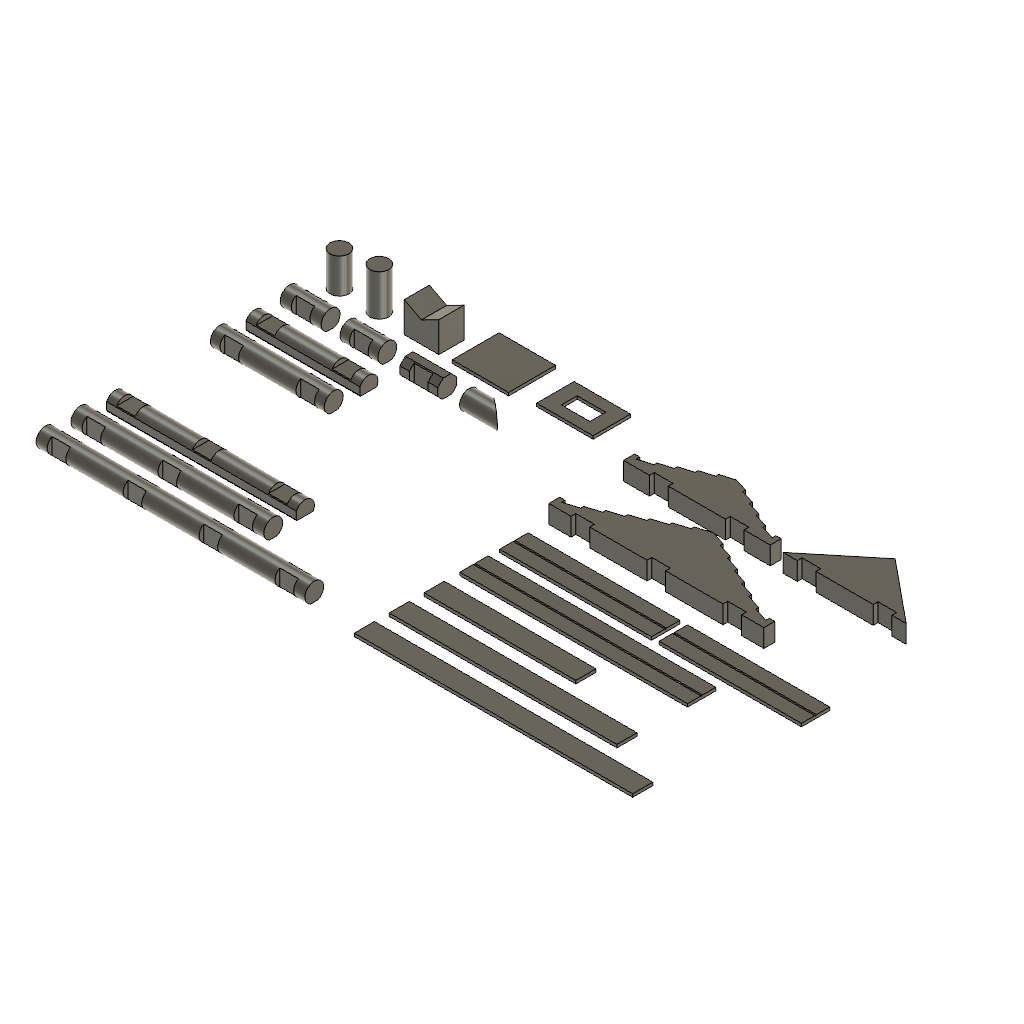
DeadPresidentTreeSections (Autodesk Fusion 360 design; units mm, degrees)
part number: 2026-11-11-17-31-42-128
part number: 2026-11-11-17-31-43-518
part number: 2026-11-11-17-31-43-754
part number: 2026-11-11-17-31-43-862
part number: 2026-11-11-17-31-44-050
part number: 2026-11-11-17-31-44-207
part number: 2026-11-11-17-31-44-370
part number: 2026-11-11-17-31-44-535
part number: 2026-11-11-17-31-44-714
part number: 2026-11-11-17-31-44-916
part number: 2026-11-11-17-31-45-037
part number: 2026-11-11-17-31-45-072
part number: 2026-11-11-17-31-45-145
part number: 2026-11-11-17-31-45-541
part number: 2026-11-11-17-31-45-973
part number: 2026-11-11-17-31-46-214
part number: 2026-11-11-17-31-46-323
part number: 2026-11-11-17-31-46-435
part number: 2026-11-11-17-31-46-554
part number: 2026-11-11-17-31-46-788
part number: 2026-11-11-17-31-47-025
part number: 2026-11-11-17-31-47-289
part number: 2026-11-11-17-31-47-724
part number: 2026-11-11-17-31-47-905
Autodesk Fusion 360 part; units mm, degrees
(part 1 of 2)
sketch "Section" plane through (0, 0, 0) normal (1, 0, 0) x (0, 0, -1) in component "log_1insert_1-5_8"
  circle A0 centre (-8.725, 0) radius 9.525
  line L0 (0, -3.821) -> (0, 3.821)
  dimension "d21" = 8.725
  dimension "d22" = 19.05
  constraint horizontal origin A0.centre
  constraint coincident A0 L0.start
  constraint coincident A0 L0.end
  constraint coincident origin L0
  constraint vertical L0
  measures "d21" horizontal distance of origin A0.centre
  measures "d22" diameter of A0
extrude "Log" add sketch "Section" along normal blind 41.275 contours A0 L0 picked at (-13.8021, 0.6968) makes body 1 in component "log_1insert_1-5_8"
sketch "Notch" plane through (0, 0, 0) normal (0, 0, 1) x (1, 0, 0) in component "log_1insert_1-5_8"
  line L0 (11.3125, 4.7625) -> (29.9625, 4.7625)
  line L1 (29.9625, 4.7625) -> (29.9625, 10.525)
  line L2 (29.9625, 10.525) -> (11.3125, 10.525)
  line L3 (11.3125, 10.525) -> (11.3125, 4.7625)
  line L4 (11.3125, -4.7625) -> (29.9625, -4.7625)
  line L5 (29.9625, -4.7625) -> (29.9625, -10.525)
  line L6 (29.9625, -10.525) -> (11.3125, -10.525)
  line L7 (11.3125, -10.525) -> (11.3125, -4.7625)
  dimension "d25" = 11.3125
  dimension "d26" = 4.7625
  dimension "d27" = 29.9625
  dimension "d28" = 10.525
  dimension "d29" = 11.3125
  dimension "d30" = 4.7625
  dimension "d31" = 29.9625
  dimension "d32" = 10.525
  constraint horizontal L0
  constraint vertical L1
  constraint horizontal L2
  constraint vertical L3
  constraint horizontal L4
  constraint vertical L5
  constraint horizontal L6
  constraint vertical L7
  measures "d25" horizontal distance of origin L0.start
  measures "d26" vertical distance of origin L0.start
  measures "d27" horizontal distance of origin L1.end
  measures "d28" vertical distance of origin L1.end
  measures "d29" horizontal distance of origin L4.start
  measures "d30" vertical distance of origin L4.start
  measures "d31" horizontal distance of origin L5.end
  measures "d32" vertical distance of origin L5.end
extrude "Notch cut" cut sketch "Notch" along normal blind 19.05 bodies 1 in component "log_1insert_1-5_8"
pattern_linear "Notch pattern" count 2 spacing 0.001 along (1, 0, 0) count 3 spacing 0 along (1, 0, 0) of "Notch cut" in component "log_1insert_1-5_8"
sketch "Section (2)" plane through (0, 0, 0) normal (1, 0, 0) x (0, 0, -1) in component "log_1insert_1-1_2_round"
  circle A0 centre (-8.725, 0) radius 9.525
  line L0 (0, -3.821) -> (0, 3.821)
  dimension "d43" = 8.725
  dimension "d44" = 19.05
  constraint horizontal origin A0.centre
  constraint coincident A0 L0.start
  constraint coincident A0 L0.end
  constraint coincident origin L0
  constraint vertical L0
  measures "d43" horizontal distance of origin A0.centre
  measures "d44" diameter of A0
extrude "Log'" add sketch "Section (2)" along normal blind 38.1 separate body contours A0 L0 picked at (-13.8021, 0.6968) makes body 2 in component "log_1insert_1-1_2_round"
sketch "Notch (2)" plane through (0, 0, 0) normal (0, 0, 1) x (1, 0, 0) in component "log_1insert_1-1_2_round"
  line L0 (9.725, 4.7625) -> (28.375, 4.7625)
  line L1 (28.375, 4.7625) -> (28.375, 10.525)
  line L2 (28.375, 10.525) -> (9.725, 10.525)
  line L3 (9.725, 10.525) -> (9.725, 4.7625)
  line L4 (9.725, -4.7625) -> (28.375, -4.7625)
  line L5 (28.375, -4.7625) -> (28.375, -10.525)
  line L6 (28.375, -10.525) -> (9.725, -10.525)
  line L7 (9.725, -10.525) -> (9.725, -4.7625)
  dimension "d47" = 9.725
  dimension "d48" = 4.7625
  dimension "d49" = 28.375
  dimension "d50" = 10.525
  dimension "d51" = 9.725
  dimension "d52" = 4.7625
  dimension "d53" = 28.375
  dimension "d54" = 10.525
  constraint horizontal L0
  constraint vertical L1
  constraint horizontal L2
  constraint vertical L3
  constraint horizontal L4
  constraint vertical L5
  constraint horizontal L6
  constraint vertical L7
  measures "d47" horizontal distance of origin L0.start
  measures "d48" vertical distance of origin L0.start
  measures "d49" horizontal distance of origin L1.end
  measures "d50" vertical distance of origin L1.end
  measures "d51" horizontal distance of origin L4.start
  measures "d52" vertical distance of origin L4.start
  measures "d53" horizontal distance of origin L5.end
  measures "d54" vertical distance of origin L5.end
extrude "Notch cut'" cut sketch "Notch (2)" along normal blind 19.05 bodies 2 in component "log_1insert_1-1_2_round"
pattern_linear "Notch pattern'" count 2 spacing 0.001 along (1, 0, 0) count 3 spacing 0 along (1, 0, 0) of "Notch cut'" in component "log_1insert_1-1_2_round"
sketch "Section (3)" plane through (0, 0, 0) normal (1, 0, 0) x (0, 0, -1) in component "log_1insert_1-1_2_octagonal"
  line L0 (0.8, -9.525) -> (0.8, 9.525)
  line L1 (0.8, 9.525) -> (-18.25, 9.525)
  line L2 (-18.25, 9.525) -> (-18.25, -9.525)
  line L3 (-18.25, -9.525) -> (0.8, -9.525)
  dimension "d65" = 9.525
  dimension "d66" = 0.8
  dimension "d67" = 9.525
  dimension "d68" = 18.25
  constraint vertical L0
  constraint horizontal L1
  constraint vertical L2
  constraint horizontal L3
  measures "d65" vertical distance of origin L0.start
  measures "d66" horizontal distance of origin L0.start
  measures "d67" vertical distance of origin L1.end
  measures "d68" horizontal distance of origin L1.end
extrude "Log''" add sketch "Section (3)" along normal blind 38.1 separate body makes body 3 in component "log_1insert_1-1_2_octagonal"
chamfer "Octagon corners" distance 5.5796 angle 45 4 edges at (19.05, -9.525, 18.25) (19.05, 9.525, 18.25) (19.05, 9.525, -0.8) (19.05, -9.525, -0.8) tangent chain off on bodies 3 in component "log_1insert_1-1_2_octagonal"
sketch "Printing flat" plane through (0, 0, 0) normal (1, 0, 0) x (0, 0, -1) in component "log_1insert_1-1_2_octagonal"
  line L0 (1.8, -10.525) -> (1.8, 10.525)
  line L1 (1.8, 10.525) -> (0, 10.525)
  line L2 (0, 10.525) -> (0, -10.525)
  line L3 (0, -10.525) -> (1.8, -10.525)
  dimension "d72" = 10.525
  dimension "d73" = 1.8
  dimension "d74" = 10.525
  constraint vertical L0
  constraint horizontal L1
  constraint vertical L2
  constraint horizontal L3
  constraint vertical origin L1.end
  measures "d72" vertical distance of origin L0.start
  measures "d73" horizontal distance of origin L0.start
  measures "d74" vertical distance of origin L1.end
extrude "Printing flat (1)" cut sketch "Printing flat" along normal blind 38.1 bodies 3 in component "log_1insert_1-1_2_octagonal"
sketch "Notch (3)" plane through (0, 0, 0) normal (0, 0, 1) x (1, 0, 0) in component "log_1insert_1-1_2_octagonal"
  line L0 (9.725, 4.7625) -> (28.375, 4.7625)
  line L1 (28.375, 4.7625) -> (28.375, 10.525)
  line L2 (28.375, 10.525) -> (9.725, 10.525)
  line L3 (9.725, 10.525) -> (9.725, 4.7625)
  line L4 (9.725, -4.7625) -> (28.375, -4.7625)
  line L5 (28.375, -4.7625) -> (28.375, -10.525)
  line L6 (28.375, -10.525) -> (9.725, -10.525)
  line L7 (9.725, -10.525) -> (9.725, -4.7625)
  dimension "d77" = 9.725
  dimension "d78" = 4.7625
  dimension "d79" = 28.375
  dimension "d80" = 10.525
  dimension "d81" = 9.725
  dimension "d82" = 4.7625
  dimension "d83" = 28.375
  dimension "d84" = 10.525
  constraint horizontal L0
  constraint vertical L1
  constraint horizontal L2
  constraint vertical L3
  constraint horizontal L4
  constraint vertical L5
  constraint horizontal L6
  constraint vertical L7
  measures "d77" horizontal distance of origin L0.start
  measures "d78" vertical distance of origin L0.start
  measures "d79" horizontal distance of origin L1.end
  measures "d80" vertical distance of origin L1.end
  measures "d81" horizontal distance of origin L4.start
  measures "d82" vertical distance of origin L4.start
  measures "d83" horizontal distance of origin L5.end
  measures "d84" vertical distance of origin L5.end
extrude "Notch cut''" cut sketch "Notch (3)" along normal blind 19.05 bodies 3 in component "log_1insert_1-1_2_octagonal"
pattern_linear "Notch pattern''" count 2 spacing 0.001 along (1, 0, 0) count 3 spacing 0 along (1, 0, 0) of "Notch cut''" in component "log_1insert_1-1_2_octagonal"
sketch "Section (4)" plane through (0, 0, 0) normal (1, 0, 0) x (0, 0, -1) in component "log_2insert_4-1_2"
  circle A0 centre (-8.725, 0) radius 9.525
  line L0 (0, -3.821) -> (0, 3.821)
  dimension "d95" = 8.725
  dimension "d96" = 19.05
  constraint horizontal origin A0.centre
  constraint coincident A0 L0.start
  constraint coincident A0 L0.end
  constraint coincident origin L0
  constraint vertical L0
  measures "d95" horizontal distance of origin A0.centre
  measures "d96" diameter of A0
extrude "Log'''" add sketch "Section (4)" along normal blind 114.3 separate body contours A0 L0 picked at (-13.8021, 0.6968) makes body 4 in component "log_2insert_4-1_2"
sketch "Notch (4)" plane through (0, 0, 0) normal (0, 0, 1) x (1, 0, 0) in component "log_2insert_4-1_2"
  line L0 (9.725, 4.7625) -> (28.375, 4.7625)
  line L1 (28.375, 4.7625) -> (28.375, 10.525)
  line L2 (28.375, 10.525) -> (9.725, 10.525)
  line L3 (9.725, 10.525) -> (9.725, 4.7625)
  line L4 (9.725, -4.7625) -> (28.375, -4.7625)
  line L5 (28.375, -4.7625) -> (28.375, -10.525)
  line L6 (28.375, -10.525) -> (9.725, -10.525)
  line L7 (9.725, -10.525) -> (9.725, -4.7625)
  dimension "d99" = 9.725
  dimension "d100" = 4.7625
  dimension "d101" = 28.375
  dimension "d102" = 10.525
  dimension "d103" = 9.725
  dimension "d104" = 4.7625
  dimension "d105" = 28.375
  dimension "d106" = 10.525
  constraint horizontal L0
  constraint vertical L1
  constraint horizontal L2
  constraint vertical L3
  constraint horizontal L4
  constraint vertical L5
  constraint horizontal L6
  constraint vertical L7
  measures "d99" horizontal distance of origin L0.start
  measures "d100" vertical distance of origin L0.start
  measures "d101" horizontal distance of origin L1.end
  measures "d102" vertical distance of origin L1.end
  measures "d103" horizontal distance of origin L4.start
  measures "d104" vertical distance of origin L4.start
  measures "d105" horizontal distance of origin L5.end
  measures "d106" vertical distance of origin L5.end
extrude "Notch cut'''" cut sketch "Notch (4)" along normal blind 19.05 bodies 4 in component "log_2insert_4-1_2"
pattern_linear "Notch pattern'''" count 2 spacing 76.2 along (1, 0, 0) count 3 spacing 0 along (1, 0, 0) of "Notch cut'''" in component "log_2insert_4-1_2"
sketch "Section (5)" plane through (0, 0, 0) normal (1, 0, 0) x (0, 0, -1) in component "log_3insert_7-5_8"
  circle A0 centre (-8.725, 0) radius 9.525
  line L0 (0, -3.821) -> (0, 3.821)
  dimension "d117" = 8.725
  dimension "d118" = 19.05
  constraint horizontal origin A0.centre
  constraint coincident A0 L0.start
  constraint coincident A0 L0.end
  constraint coincident origin L0
  constraint vertical L0
  measures "d117" horizontal distance of origin A0.centre
  measures "d118" diameter of A0
extrude "Log''''" add sketch "Section (5)" along normal blind 193.675 separate body contours A0 L0 picked at (-13.8021, 0.6968) makes body 5 in component "log_3insert_7-5_8"
sketch "Notch (5)" plane through (0, 0, 0) normal (0, 0, 1) x (1, 0, 0) in component "log_3insert_7-5_8"
  line L0 (11.3125, 4.7625) -> (29.9625, 4.7625)
  line L1 (29.9625, 4.7625) -> (29.9625, 10.525)
  line L2 (29.9625, 10.525) -> (11.3125, 10.525)
  line L3 (11.3125, 10.525) -> (11.3125, 4.7625)
  line L4 (11.3125, -4.7625) -> (29.9625, -4.7625)
  line L5 (29.9625, -4.7625) -> (29.9625, -10.525)
  line L6 (29.9625, -10.525) -> (11.3125, -10.525)
  line L7 (11.3125, -10.525) -> (11.3125, -4.7625)
  dimension "d121" = 11.3125
  dimension "d122" = 4.7625
  dimension "d123" = 29.9625
  dimension "d124" = 10.525
  dimension "d125" = 11.3125
  dimension "d126" = 4.7625
  dimension "d127" = 29.9625
  dimension "d128" = 10.525
  constraint horizontal L0
  constraint vertical L1
  constraint horizontal L2
  constraint vertical L3
  constraint horizontal L4
  constraint vertical L5
  constraint horizontal L6
  constraint vertical L7
  measures "d121" horizontal distance of origin L0.start
  measures "d122" vertical distance of origin L0.start
  measures "d123" horizontal distance of origin L1.end
  measures "d124" vertical distance of origin L1.end
  measures "d125" horizontal distance of origin L4.start
  measures "d126" vertical distance of origin L4.start
  measures "d127" horizontal distance of origin L5.end
  measures "d128" vertical distance of origin L5.end
extrude "Notch cut''''" cut sketch "Notch (5)" along normal blind 19.05 bodies 5 in component "log_3insert_7-5_8"
pattern_linear "Notch pattern''''" count 3 spacing 76.2 along (1, 0, 0) count 3 spacing 0 along (1, 0, 0) of "Notch cut''''" in component "log_3insert_7-5_8"
sketch "Section (6)" plane through (0, 0, 0) normal (1, 0, 0) x (0, 0, -1) in component "log_4insert_10-5_8"
  circle A0 centre (-8.725, 0) radius 9.525
  line L0 (0, -3.821) -> (0, 3.821)
  dimension "d139" = 8.725
  dimension "d140" = 19.05
  constraint horizontal origin A0.centre
  constraint coincident A0 L0.start
  constraint coincident A0 L0.end
  constraint coincident origin L0
  constraint vertical L0
  measures "d139" horizontal distance of origin A0.centre
  measures "d140" diameter of A0
extrude "Log'''''" add sketch "Section (6)" along normal blind 269.875 separate body contours A0 L0 picked at (-13.8021, 0.6968) makes body 6 in component "log_4insert_10-5_8"
sketch "Notch (6)" plane through (0, 0, 0) normal (0, 0, 1) x (1, 0, 0) in component "log_4insert_10-5_8"
  line L0 (11.3125, 4.7625) -> (29.9625, 4.7625)
  line L1 (29.9625, 4.7625) -> (29.9625, 10.525)
  line L2 (29.9625, 10.525) -> (11.3125, 10.525)
  line L3 (11.3125, 10.525) -> (11.3125, 4.7625)
  line L4 (11.3125, -4.7625) -> (29.9625, -4.7625)
  line L5 (29.9625, -4.7625) -> (29.9625, -10.525)
  line L6 (29.9625, -10.525) -> (11.3125, -10.525)
  line L7 (11.3125, -10.525) -> (11.3125, -4.7625)
  dimension "d143" = 11.3125
  dimension "d144" = 4.7625
  dimension "d145" = 29.9625
  dimension "d146" = 10.525
  dimension "d147" = 11.3125
  dimension "d148" = 4.7625
  dimension "d149" = 29.9625
  dimension "d150" = 10.525
  constraint horizontal L0
  constraint vertical L1
  constraint horizontal L2
  constraint vertical L3
  constraint horizontal L4
  constraint vertical L5
  constraint horizontal L6
  constraint vertical L7
  measures "d143" horizontal distance of origin L0.start
  measures "d144" vertical distance of origin L0.start
  measures "d145" horizontal distance of origin L1.end
  measures "d146" vertical distance of origin L1.end
  measures "d147" horizontal distance of origin L4.start
  measures "d148" vertical distance of origin L4.start
  measures "d149" horizontal distance of origin L5.end
  measures "d150" vertical distance of origin L5.end
extrude "Notch cut'''''" cut sketch "Notch (6)" along normal blind 19.05 bodies 6 in component "log_4insert_10-5_8"
pattern_linear "Notch pattern'''''" count 4 spacing 76.2 along (1, 0, 0) count 3 spacing 0 along (1, 0, 0) of "Notch cut'''''" in component "log_4insert_10-5_8"
sketch "Section (7)" plane through (0, 0, 0) normal (1, 0, 0) x (0, 0, -1) in component "half_log_4-1_2"
  circle A0 centre (-4.7625, 0) radius 9.525
  line L0 (0, -8.2489) -> (0, 8.2489)
  dimension "d161" = 4.7625
  dimension "d162" = 19.05
  constraint horizontal origin A0.centre
  constraint coincident A0 L0.start
  constraint coincident A0 L0.end
  constraint coincident origin L0
  constraint vertical L0
  measures "d161" horizontal distance of origin A0.centre
  measures "d162" diameter of A0
extrude "Log''''''" add sketch "Section (7)" along normal blind 114.3 separate body contours A0 L0 picked at (-7.0899, 2.1595) makes body 7 in component "half_log_4-1_2"
sketch "Side flat" plane through (0, 0, 0) normal (1, 0, 0) x (0, 0, -1) in component "half_log_4-1_2"
  line L0 (1, -10.525) -> (1, -8.725)
  line L1 (1, -8.725) -> (-15.2875, -8.725)
  line L2 (-15.2875, -8.725) -> (-15.2875, -10.525)
  line L3 (-15.2875, -10.525) -> (1, -10.525)
  dimension "d165" = 10.525
  dimension "d166" = 1
  dimension "d167" = 8.725
  dimension "d168" = 15.2875
  constraint vertical L0
  constraint horizontal L1
  constraint vertical L2
  constraint horizontal L3
  measures "d165" vertical distance of origin L0.start
  measures "d166" horizontal distance of origin L0.start
  measures "d167" vertical distance of origin L1.end
  measures "d168" horizontal distance of origin L1.end
extrude "Side flat (1)" cut sketch "Side flat" along normal blind 114.3 bodies 7 in component "half_log_4-1_2"
sketch "Notch (7)" plane through (0, 0, 0) normal (0, 1, 0) x (1, 0, 0) in component "half_log_4-1_2"
  line L0 (9.725, -9.525) -> (28.375, -9.525)
  line L1 (28.375, -9.525) -> (28.375, -15.2875)
  line L2 (28.375, -15.2875) -> (9.725, -15.2875)
  line L3 (9.725, -15.2875) -> (9.725, -9.525)
  dimension "d171" = 9.725
  dimension "d172" = 9.525
  dimension "d173" = 28.375
  dimension "d174" = 15.2875
  constraint horizontal L0
  constraint vertical L1
  constraint horizontal L2
  constraint vertical L3
  measures "d171" horizontal distance of origin L0.start
  measures "d172" vertical distance of origin L0.start
  measures "d173" horizontal distance of origin L1.end
  measures "d174" vertical distance of origin L1.end
extrude "Notch cut''''''" cut sketch "Notch (7)" along normal mid plane 21.05 bodies 7 in component "half_log_4-1_2"
pattern_linear "Notch pattern''''''" count 2 spacing 76.2 along (1, 0, 0) count 3 spacing 0 along (1, 0, 0) of "Notch cut''''''" in component "half_log_4-1_2"
sketch "Section (8)" plane through (0, 0, 0) normal (1, 0, 0) x (0, 0, -1) in component "half_log_7-1_2"
  circle A0 centre (-4.7625, 0) radius 9.525
  line L0 (0, -8.2489) -> (0, 8.2489)
  dimension "d185" = 4.7625
  dimension "d186" = 19.05
  constraint horizontal origin A0.centre
  constraint coincident A0 L0.start
  constraint coincident A0 L0.end
  constraint coincident origin L0
  constraint vertical L0
  measures "d185" horizontal distance of origin A0.centre
  measures "d186" diameter of A0
extrude "Log'''''''" add sketch "Section (8)" along normal blind 190.5 separate body contours A0 L0 picked at (-7.0899, 2.1595) makes body 8 in component "half_log_7-1_2"
sketch "Side flat (2)" plane through (0, 0, 0) normal (1, 0, 0) x (0, 0, -1) in component "half_log_7-1_2"
  line L0 (1, -10.525) -> (1, -8.725)
  line L1 (1, -8.725) -> (-15.2875, -8.725)
  line L2 (-15.2875, -8.725) -> (-15.2875, -10.525)
  line L3 (-15.2875, -10.525) -> (1, -10.525)
  dimension "d189" = 10.525
  dimension "d190" = 1
  dimension "d191" = 8.725
  dimension "d192" = 15.2875
  constraint vertical L0
  constraint horizontal L1
  constraint vertical L2
  constraint horizontal L3
  measures "d189" vertical distance of origin L0.start
  measures "d190" horizontal distance of origin L0.start
  measures "d191" vertical distance of origin L1.end
  measures "d192" horizontal distance of origin L1.end
extrude "Side flat (1)'" cut sketch "Side flat (2)" along normal blind 190.5 bodies 8 in component "half_log_7-1_2"
sketch "Notch (8)" plane through (0, 0, 0) normal (0, 1, 0) x (1, 0, 0) in component "half_log_7-1_2"
  line L0 (9.725, -9.525) -> (28.375, -9.525)
  line L1 (28.375, -9.525) -> (28.375, -15.2875)
  line L2 (28.375, -15.2875) -> (9.725, -15.2875)
  line L3 (9.725, -15.2875) -> (9.725, -9.525)
  dimension "d195" = 9.725
  dimension "d196" = 9.525
  dimension "d197" = 28.375
  dimension "d198" = 15.2875
  constraint horizontal L0
  constraint vertical L1
  constraint horizontal L2
  constraint vertical L3
  measures "d195" horizontal distance of origin L0.start
  measures "d196" vertical distance of origin L0.start
  measures "d197" horizontal distance of origin L1.end
  measures "d198" vertical distance of origin L1.end
extrude "Notch cut'''''''" cut sketch "Notch (8)" along normal mid plane 21.05 bodies 8 in component "half_log_7-1_2"
pattern_linear "Notch pattern'''''''" count 3 spacing 76.2 along (1, 0, 0) count 3 spacing 0 along (1, 0, 0) of "Notch cut'''''''" in component "half_log_7-1_2"
sketch "Section (9)" plane through (0, 0, 0) normal (1, 0, 0) x (0, 0, -1) in component "beveled_end_1-1_2"
  circle A0 centre (-8.725, 0) radius 9.525
  line L0 (0, -3.821) -> (0, 3.821)
  dimension "d207" = 8.725
  dimension "d208" = 19.05
  constraint horizontal origin A0.centre
  constraint coincident A0 L0.start
  constraint coincident A0 L0.end
  constraint coincident origin L0
  constraint vertical L0
  measures "d207" horizontal distance of origin A0.centre
  measures "d208" diameter of A0
extrude "Log''''''''" add sketch "Section (9)" along normal blind 38.1 separate body contours A0 L0 picked at (-13.8021, 0.6968) makes body 9 in component "beveled_end_1-1_2"
sketch "Slant" plane through (0, 0, 0) normal (0, 0, 1) x (1, 0, 0) in component "beveled_end_1-1_2"
  line L0 (38.1, -9.525) -> (38.1, 9.525)
  line L1 (38.1, 9.525) -> (14.5752, 9.525)
  line L2 (14.5752, 9.525) -> (38.1, -9.525)
  dimension "d211" = 38.1
  dimension "d212" = 9.525
  dimension "d213" = 9.525
  dimension "d214" = 14.5752
  constraint vertical L0.start L0.end
  constraint horizontal L0.end L1.end
  measures "d211" horizontal distance of origin L0.start
  measures "d212" vertical distance of origin L0.start
  measures "d213" vertical distance of origin L0.end
  measures "d214" horizontal distance of origin L1.end
extrude "Slanted end" cut sketch "Slant" along normal blind 19.05 bodies 9 in component "beveled_end_1-1_2"
sketch "Section (10)" plane through (0, 0, 0) normal (0, 0, 1) x (1, 0, 0) in component "solid_log_1-3_8"
  circle A0 centre (0, 0) radius 9.525
  dimension "d218" = 19.05
  measures "d218" diameter of A0
extrude "Log'''''''''" add sketch "Section (10)" along normal blind 34.925 separate body makes body 10 in component "solid_log_1-3_8"
sketch "Section (11)" plane through (0, 0, 0) normal (0, 0, 1) x (1, 0, 0) in component "solid_log_1-5_8"
  circle A0 centre (0, 0) radius 9.525
  dimension "d222" = 19.05
  measures "d222" diameter of A0
extrude "Log''''''''''" add sketch "Section (11)" along normal blind 41.275 separate body makes body 11 in component "solid_log_1-5_8"
sketch "Half profile" plane through (0, 0, 0) normal (0, 0, 1) x (1, 0, 0) in component "gable_plastic_8-1_2"
  line L0 (0, 0) -> (107.95, 0)
  line L1 (107.95, 0) -> (107.95, 60.05)
  line L2 (107.95, 60.05) -> (5.4, 7.5)
  line L3 (5.4, 7.5) -> (5.4, 11.1)
  line L4 (5.4, 11.1) -> (0, 11.1)
  line L5 (0, 11.1) -> (0, 0)
  dimension "d252" = 107.95
  dimension "d253" = 60.05
  dimension "d254" = 5.4
  dimension "d255" = 7.5
  dimension "d256" = 11.1
  constraint coincident L0.start L5.end
  constraint horizontal L0.start L0.end
  constraint vertical L0.end L1.end
  constraint vertical L2.end L3.end
  constraint vertical L0.start L4.end
  constraint horizontal L3.end L4.end
  measures "d252" horizontal distance of L0.start L0.end
  measures "d253" vertical distance of L0.start L1.end
  measures "d254" horizontal distance of L0.start L2.end
  measures "d255" vertical distance of L0.start L2.end
  measures "d256" vertical distance of L0.start L3.end
extrude "Half gable" add sketch "Half profile" along normal blind 18.25 separate body makes body 12 in component "gable_plastic_8-1_2"
sketch "Step" plane through (0, 0, 0) normal (0, 0, 1) x (1, 0, 0) in component "gable_plastic_8-1_2"
  line L0 (5.4, 7.5) -> (20.05, 15.0071)
  line L1 (20.05, 15.0071) -> (20.05, 12.1071)
  line L2 (20.05, 12.1071) -> (5.4, 7.5)
  dimension "d259" = 5.4
  dimension "d260" = 7.5
  dimension "d261" = 20.05
  dimension "d262" = 15.0071
  dimension "d263" = 12.1071
  constraint vertical L0.end L1.end
  measures "d259" horizontal distance of origin L0.start
  measures "d260" vertical distance of origin L0.start
  measures "d261" horizontal distance of origin L0.end
  measures "d262" vertical distance of origin L0.end
  measures "d263" vertical distance of origin L1.end
extrude "Step cut" cut sketch "Step" along normal blind 18.25 bodies 12 in component "gable_plastic_8-1_2"
pattern_linear "Step pattern" count 7 spacing 16.4615 along (0.889957, 0.456044, 0) count 3 spacing 0 along (0.889957, 0.456044, 0) of "Step cut" in component "gable_plastic_8-1_2"
ref_plane "WorkPlane1" through (107.95, 0, 0) normal (1, 0, 0) x (0, 1, 0) in component "gable_plastic_8-1_2"
mirror "Mirror half" about plane through (107.95, 0, 0) normal (1, 0, 0) of bodies 12 merged in component "gable_plastic_8-1_2"
sketch "Notch (9)" plane through (0, 0, 0) normal (0, 0, 1) x (1, 0, 0) in component "gable_plastic_8-1_2"
  line L0 (22.425, -1) -> (41.075, -1)
  line L1 (41.075, -1) -> (41.075, 4.7625)
  line L2 (41.075, 4.7625) -> (22.425, 4.7625)
  line L3 (22.425, 4.7625) -> (22.425, -1)
  dimension "d274" = 22.425
  dimension "d275" = 1
  dimension "d276" = 41.075
  dimension "d277" = 4.7625
  constraint horizontal L0
  constraint vertical L1
  constraint horizontal L2
  constraint vertical L3
  measures "d274" horizontal distance of origin L0.start
  measures "d275" vertical distance of origin L0.start
  measures "d276" horizontal distance of origin L1.end
  measures "d277" vertical distance of origin L1.end
extrude "Notch cut''''''''" cut sketch "Notch (9)" along normal blind 18.25 bodies 12 in component "gable_plastic_8-1_2"
pattern_linear "Notch pattern''''''''" count 3 spacing 76.2 along (1, 0, 0) count 3 spacing 0 along (1, 0, 0) of "Notch cut''''''''" in component "gable_plastic_8-1_2"
sketch "Half profile (2)" plane through (0, 0, 0) normal (0, 0, 1) x (1, 0, 0) in component "gable_plastic_small_2notch"
  line L0 (0, 0) -> (73.66, 0)
  line L1 (73.66, 0) -> (73.66, 42.4787)
  line L2 (73.66, 42.4787) -> (5.4, 7.5)
  line L3 (5.4, 7.5) -> (5.4, 11.1)
  line L4 (5.4, 11.1) -> (0, 11.1)
  line L5 (0, 11.1) -> (0, 0)
  dimension "d284" = 73.66
  dimension "d285" = 42.4787
  dimension "d286" = 5.4
  dimension "d287" = 7.5
  dimension "d288" = 11.1
  constraint coincident L0.start L5.end
  constraint horizontal L0.start L0.end
  constraint vertical L0.end L1.end
  constraint vertical L2.end L3.end
  constraint vertical L0.start L4.end
  constraint horizontal L3.end L4.end
  measures "d284" horizontal distance of L0.start L0.end
  measures "d285" vertical distance of L0.start L1.end
  measures "d286" horizontal distance of L0.start L2.end
  measures "d287" vertical distance of L0.start L2.end
  measures "d288" vertical distance of L0.start L3.end
extrude "Half gable'" add sketch "Half profile (2)" along normal blind 18.25 separate body makes body 13 in component "gable_plastic_small_2notch"
sketch "Step (2)" plane through (0, 0, 0) normal (0, 0, 1) x (1, 0, 0) in component "gable_plastic_small_2notch"
  line L0 (5.4, 7.5) -> (19.052, 14.4957)
  line L1 (19.052, 14.4957) -> (19.052, 11.5957)
  line L2 (19.052, 11.5957) -> (5.4, 7.5)
  dimension "d291" = 5.4
  dimension "d292" = 7.5
  dimension "d293" = 19.052
  dimension "d294" = 14.4957
  dimension "d295" = 11.5957
  constraint vertical L0.end L1.end
  measures "d291" horizontal distance of origin L0.start
  measures "d292" vertical distance of origin L0.start
  measures "d293" horizontal distance of origin L0.end
  measures "d294" vertical distance of origin L0.end
  measures "d295" vertical distance of origin L1.end
extrude "Step cut'" cut sketch "Step (2)" along normal blind 18.25 bodies 13 in component "gable_plastic_small_2notch"
pattern_linear "Step pattern'" count 5 spacing 15.3401 along (0.889957, 0.456044, 0) count 3 spacing 0 along (0.889957, 0.456044, 0) of "Step cut'" in component "gable_plastic_small_2notch"
ref_plane "WorkPlane1" through (73.66, 0, 0) normal (1, 0, 0) x (0, 1, 0) in component "gable_plastic_small_2notch"
mirror "Mirror half'" about plane through (73.66, 0, 0) normal (1, 0, 0) of bodies 13 merged in component "gable_plastic_small_2notch"
sketch "Notch (10)" plane through (0, 0, 0) normal (0, 0, 1) x (1, 0, 0) in component "gable_plastic_small_2notch"
  line L0 (26.235, -1) -> (44.885, -1)
  line L1 (44.885, -1) -> (44.885, 4.7625)
  line L2 (44.885, 4.7625) -> (26.235, 4.7625)
  line L3 (26.235, 4.7625) -> (26.235, -1)
  dimension "d306" = 26.235
  dimension "d307" = 1
  dimension "d308" = 44.885
  dimension "d309" = 4.7625
  constraint horizontal L0
  constraint vertical L1
  constraint horizontal L2
  constraint vertical L3
  measures "d306" horizontal distance of origin L0.start
  measures "d307" vertical distance of origin L0.start
  measures "d308" horizontal distance of origin L1.end
  measures "d309" vertical distance of origin L1.end
extrude "Notch cut'''''''''" cut sketch "Notch (10)" along normal blind 18.25 bodies 13 in component "gable_plastic_small_2notch"
pattern_linear "Notch pattern'''''''''" count 2 spacing 76.2 along (1, 0, 0) count 3 spacing 0 along (1, 0, 0) of "Notch cut'''''''''" in component "gable_plastic_small_2notch"
sketch "Profile" plane through (0, 0, 0) normal (0, 0, 1) x (1, 0, 0) in component "gable_wood_triangle_4x2"
  line L0 (0, 0) -> (123.825, 0)
  line L1 (123.825, 0) -> (61.9125, 50.8)
  line L2 (61.9125, 50.8) -> (0, 0)
  dimension "d321" = 123.825
  dimension "d322" = 61.9125
  dimension "d323" = 50.8
  constraint coincident L0.start L2.end
  constraint horizontal L0.start L0.end
  measures "d321" horizontal distance of L0.start L0.end
  measures "d322" horizontal distance of L0.start L1.end
  measures "d323" vertical distance of L0.start L1.end
extrude "Gable" add sketch "Profile" along normal blind 18.25 separate body makes body 14 in component "gable_wood_triangle_4x2"
sketch "Notch (11)" plane through (0, 0, 0) normal (0, 0, 1) x (1, 0, 0) in component "gable_wood_triangle_4x2"
  line L0 (14.4875, -1) -> (33.1375, -1)
  line L1 (33.1375, -1) -> (33.1375, 4.7625)
  line L2 (33.1375, 4.7625) -> (14.4875, 4.7625)
  line L3 (14.4875, 4.7625) -> (14.4875, -1)
  dimension "d326" = 14.4875
  dimension "d327" = 1
  dimension "d328" = 33.1375
  dimension "d329" = 4.7625
  constraint horizontal L0
  constraint vertical L1
  constraint horizontal L2
  constraint vertical L3
  measures "d326" horizontal distance of origin L0.start
  measures "d327" vertical distance of origin L0.start
  measures "d328" horizontal distance of origin L1.end
  measures "d329" vertical distance of origin L1.end
extrude "Notch cut''''''''''" cut sketch "Notch (11)" along normal blind 18.25 bodies 14 in component "gable_wood_triangle_4x2"
pattern_linear "Notch pattern''''''''''" count 2 spacing 76.2 along (1, 0, 0) count 3 spacing 0 along (1, 0, 0) of "Notch cut''''''''''" in component "gable_wood_triangle_4x2"
sketch "Outline" plane through (0, 0, 0) normal (0, 0, 1) x (1, 0, 0) in component "shingle_flat_6"
  line L0 (0, -10.16) -> (152.4, -10.16)
  line L1 (152.4, -10.16) -> (152.4, 10.16)
  line L2 (152.4, 10.16) -> (0, 10.16)
  line L3 (0, 10.16) -> (0, -10.16)
  dimension "d337" = 10.16
  dimension "d338" = 152.4
  dimension "d339" = 10.16
  constraint horizontal L0
  constraint vertical L1
  constraint horizontal L2
  constraint vertical L3
  constraint vertical origin L0.start
  measures "d337" vertical distance of origin L0.start
  measures "d338" horizontal distance of origin L1.end
  measures "d339" vertical distance of origin L1.end
extrude "Board" add sketch "Outline" along normal blind 3.175 separate body makes body 15 in component "shingle_flat_6"
sketch "Outline (2)" plane through (0, 0, 0) normal (0, 0, 1) x (1, 0, 0) in component "shingle_flat_9"
  line L0 (0, -10.16) -> (228.6, -10.16)
  line L1 (228.6, -10.16) -> (228.6, 10.16)
  line L2 (228.6, 10.16) -> (0, 10.16)
  line L3 (0, 10.16) -> (0, -10.16)
  dimension "d343" = 10.16
  dimension "d344" = 228.6
  dimension "d345" = 10.16
  constraint horizontal L0
  constraint vertical L1
  constraint horizontal L2
  constraint vertical L3
  constraint vertical origin L0.start
  measures "d343" vertical distance of origin L0.start
  measures "d344" horizontal distance of origin L1.end
  measures "d345" vertical distance of origin L1.end
extrude "Board'" add sketch "Outline (2)" along normal blind 3.175 separate body makes body 16 in component "shingle_flat_9"
sketch "Outline (3)" plane through (0, 0, 0) normal (0, 0, 1) x (1, 0, 0) in component "shingle_flat_11"
  line L0 (0, -10.16) -> (279.4, -10.16)
  line L1 (279.4, -10.16) -> (279.4, 10.16)
  line L2 (279.4, 10.16) -> (0, 10.16)
  line L3 (0, 10.16) -> (0, -10.16)
  dimension "d349" = 10.16
  dimension "d350" = 279.4
  dimension "d351" = 10.16
  constraint horizontal L0
  constraint vertical L1
  constraint horizontal L2
  constraint vertical L3
  constraint vertical origin L0.start
  measures "d349" vertical distance of origin L0.start
  measures "d350" horizontal distance of origin L1.end
  measures "d351" vertical distance of origin L1.end
extrude "Board''" add sketch "Outline (3)" along normal blind 3.175 separate body makes body 17 in component "shingle_flat_11"
sketch "Outline (4)" plane through (0, 0, 0) normal (0, 0, 1) x (1, 0, 0) in component "shingle_ridge_5-5_8"
  line L0 (0, -14.2875) -> (142.875, -14.2875)
  line L1 (142.875, -14.2875) -> (142.875, 14.2875)
  line L2 (142.875, 14.2875) -> (0, 14.2875)
  line L3 (0, 14.2875) -> (0, -14.2875)
  dimension "d355" = 14.2875
  dimension "d356" = 142.875
  dimension "d357" = 14.2875
  constraint horizontal L0
  constraint vertical L1
  constraint horizontal L2
  constraint vertical L3
  constraint vertical origin L0.start
  measures "d355" vertical distance of origin L0.start
  measures "d356" horizontal distance of origin L1.end
  measures "d357" vertical distance of origin L1.end
extrude "Board'''" add sketch "Outline (4)" along normal blind 3.175 separate body makes body 18 in component "shingle_ridge_5-5_8"
sketch "Groove" plane through (0, 0, 0) normal (1, 0, 0) x (0, 0, -1) in component "shingle_ridge_5-5_8"
  line L0 (-3.175, -0.8) -> (-3.175, 0.8)
  line L1 (-3.175, 0.8) -> (-2.375, 0)
  line L2 (-2.375, 0) -> (-3.175, -0.8)
  dimension "d360" = 0.8
  dimension "d361" = 3.175
  dimension "d362" = 0.8
  dimension "d363" = 2.375
  constraint vertical L0.start L0.end
  constraint horizontal origin L1.end
  measures "d360" vertical distance of origin L0.start
  measures "d361" horizontal distance of origin L0.start
  measures "d362" vertical distance of origin L0.end
  measures "d363" horizontal distance of origin L1.end
extrude "Groove (1)" cut sketch "Groove" along normal blind 142.875 bodies 18 in component "shingle_ridge_5-5_8"
sketch "Outline (5)" plane through (0, 0, 0) normal (0, 0, 1) x (1, 0, 0) in component "shingle_ridge_6"
  line L0 (0, -14.2875) -> (152.4, -14.2875)
  line L1 (152.4, -14.2875) -> (152.4, 14.2875)
  line L2 (152.4, 14.2875) -> (0, 14.2875)
  line L3 (0, 14.2875) -> (0, -14.2875)
  dimension "d367" = 14.2875
  dimension "d368" = 152.4
  dimension "d369" = 14.2875
  constraint horizontal L0
  constraint vertical L1
  constraint horizontal L2
  constraint vertical L3
  constraint vertical origin L0.start
  measures "d367" vertical distance of origin L0.start
  measures "d368" horizontal distance of origin L1.end
  measures "d369" vertical distance of origin L1.end
extrude "Board''''" add sketch "Outline (5)" along normal blind 3.175 separate body makes body 19 in component "shingle_ridge_6"
sketch "Groove (2)" plane through (0, 0, 0) normal (1, 0, 0) x (0, 0, -1) in component "shingle_ridge_6"
  line L0 (-3.175, -0.8) -> (-3.175, 0.8)
  line L1 (-3.175, 0.8) -> (-2.375, 0)
  line L2 (-2.375, 0) -> (-3.175, -0.8)
  dimension "d372" = 0.8
  dimension "d373" = 3.175
  dimension "d374" = 0.8
  dimension "d375" = 2.375
  constraint vertical L0.start L0.end
  constraint horizontal origin L1.end
  measures "d372" vertical distance of origin L0.start
  measures "d373" horizontal distance of origin L0.start
  measures "d374" vertical distance of origin L0.end
  measures "d375" horizontal distance of origin L1.end
extrude "Groove (1)'" cut sketch "Groove (2)" along normal blind 152.4 bodies 19 in component "shingle_ridge_6"
sketch "Outline (6)" plane through (0, 0, 0) normal (0, 0, 1) x (1, 0, 0) in component "shingle_ridge_9"
  line L0 (0, -14.2875) -> (228.6, -14.2875)
  line L1 (228.6, -14.2875) -> (228.6, 14.2875)
  line L2 (228.6, 14.2875) -> (0, 14.2875)
  line L3 (0, 14.2875) -> (0, -14.2875)
  dimension "d379" = 14.2875
  dimension "d380" = 228.6
  dimension "d381" = 14.2875
  constraint horizontal L0
  constraint vertical L1
  constraint horizontal L2
  constraint vertical L3
  constraint vertical origin L0.start
  measures "d379" vertical distance of origin L0.start
  measures "d380" horizontal distance of origin L1.end
  measures "d381" vertical distance of origin L1.end
extrude "Board'''''" add sketch "Outline (6)" along normal blind 3.175 separate body makes body 20 in component "shingle_ridge_9"
sketch "Groove (3)" plane through (0, 0, 0) normal (1, 0, 0) x (0, 0, -1) in component "shingle_ridge_9"
  line L0 (-3.175, -0.8) -> (-3.175, 0.8)
  line L1 (-3.175, 0.8) -> (-2.375, 0)
  line L2 (-2.375, 0) -> (-3.175, -0.8)
  dimension "d384" = 0.8
  dimension "d385" = 3.175
  dimension "d386" = 0.8
  dimension "d387" = 2.375
  constraint vertical L0.start L0.end
  constraint horizontal origin L1.end
  measures "d384" vertical distance of origin L0.start
  measures "d385" horizontal distance of origin L0.start
  measures "d386" vertical distance of origin L0.end
  measures "d387" horizontal distance of origin L1.end
extrude "Groove (1)''" cut sketch "Groove (3)" along normal blind 228.6 bodies 20 in component "shingle_ridge_9"
sketch "Outline (7)" plane through (0, 0, 0) normal (0, 0, 1) x (1, 0, 0) in component "chimney"
  line L0 (-17.4625, -12.7) -> (17.4625, -12.7)
  line L1 (17.4625, -12.7) -> (17.4625, 12.7)
  line L2 (17.4625, 12.7) -> (-17.4625, 12.7)
  line L3 (-17.4625, 12.7) -> (-17.4625, -12.7)
  dimension "d396" = 17.4625
  dimension "d397" = 12.7
  dimension "d398" = 17.4625
  dimension "d399" = 12.7
  constraint horizontal L0
  constraint vertical L1
  constraint horizontal L2
  constraint vertical L3
  measures "d396" horizontal distance of origin L0.start
  measures "d397" vertical distance of origin L0.start
  measures "d398" horizontal distance of origin L1.end
  measures "d399" vertical distance of origin L1.end
extrude "Block" add sketch "Outline (7)" along normal blind 30.48 separate body makes body 21 in component "chimney"
sketch "Pocket" plane through (0, 0, 0) normal (0, 0, 1) x (1, 0, 0) in component "chimney"
  line L0 (-14.4145, -9.652) -> (14.4145, -9.652)
  line L1 (14.4145, -9.652) -> (14.4145, 9.652)
  line L2 (14.4145, 9.652) -> (-14.4145, 9.652)
  line L3 (-14.4145, 9.652) -> (-14.4145, -9.652)
  dimension "d402" = 14.4145
  dimension "d403" = 9.652
  dimension "d404" = 14.4145
  dimension "d405" = 9.652
  constraint horizontal L0
  constraint vertical L1
  constraint horizontal L2
  constraint vertical L3
  measures "d402" horizontal distance of origin L0.start
  measures "d403" vertical distance of origin L0.start
  measures "d404" horizontal distance of origin L1.end
  measures "d405" vertical distance of origin L1.end
extrude "Open top" cut sketch "Pocket" along normal blind 12.7 bodies 21 in component "chimney"
sketch "Ridge V" plane through (0, 0, 0) normal (0, 1, 0) x (1, 0, 0) in component "chimney"
  line L0 (-17.4625, -30.48) -> (17.4625, -30.48)
  line L1 (17.4625, -30.48) -> (0, -21.5316)
  line L2 (0, -21.5316) -> (-17.4625, -30.48)
  dimension "d408" = 17.4625
  dimension "d409" = 30.48
  dimension "d410" = 17.4625
  dimension "d411" = 21.5316
  constraint horizontal L0.start L0.end
  constraint vertical origin L1.end
  measures "d408" horizontal distance of origin L0.start
  measures "d409" vertical distance of origin L0.start
  measures "d410" horizontal distance of origin L0.end
  measures "d411" vertical distance of origin L1.end
extrude "Ridge V cut" cut sketch "Ridge V" along normal mid plane 27.4 bodies 21 in component "chimney"
sketch "Outline (8)" plane through (0, 0, 0) normal (0, 0, 1) x (1, 0, 0) in component "extra_door"
  line L0 (-28.375, -23.6125) -> (28.375, -23.6125)
  line L1 (28.375, -23.6125) -> (28.375, 23.6125)
  line L2 (28.375, 23.6125) -> (-28.375, 23.6125)
  line L3 (-28.375, 23.6125) -> (-28.375, -23.6125)
  dimension "d417" = 28.375
  dimension "d418" = 23.6125
  dimension "d419" = 28.375
  dimension "d420" = 23.6125
  constraint horizontal L0
  constraint vertical L1
  constraint horizontal L2
  constraint vertical L3
  measures "d417" horizontal distance of origin L0.start
  measures "d418" vertical distance of origin L0.start
  measures "d419" horizontal distance of origin L1.end
  measures "d420" vertical distance of origin L1.end
extrude "Panel" add sketch "Outline (8)" along normal blind 3.175 separate body makes body 22 in component "extra_door"
sketch "Outline (9)" plane through (0, 0, 0) normal (0, 0, 1) x (1, 0, 0) in component "extra_window"
  line L0 (-28.375, -18.85) -> (28.375, -18.85)
  line L1 (28.375, -18.85) -> (28.375, 18.85)
  line L2 (28.375, 18.85) -> (-28.375, 18.85)
  line L3 (-28.375, 18.85) -> (-28.375, -18.85)
  line L4 (-14.2875, -7.9375) -> (14.2875, -7.9375)
  line L5 (14.2875, -7.9375) -> (14.2875, 7.9375)
  line L6 (14.2875, 7.9375) -> (-14.2875, 7.9375)
  line L7 (-14.2875, 7.9375) -> (-14.2875, -7.9375)
  dimension "d428" = 28.375
  dimension "d429" = 18.85
  dimension "d430" = 28.375
  dimension "d431" = 18.85
  dimension "d432" = 14.2875
  dimension "d433" = 7.9375
  dimension "d434" = 14.2875
  dimension "d435" = 7.9375
  constraint horizontal L0
  constraint vertical L1
  constraint horizontal L2
  constraint vertical L3
  constraint horizontal L4
  constraint vertical L5
  constraint horizontal L6
  constraint vertical L7
  measures "d428" horizontal distance of origin L0.start
  measures "d429" vertical distance of origin L0.start
  measures "d430" horizontal distance of origin L1.end
  measures "d431" vertical distance of origin L1.end
  measures "d432" horizontal distance of origin L4.start
  measures "d433" vertical distance of origin L4.start
  measures "d434" horizontal distance of origin L5.end
  measures "d435" vertical distance of origin L5.end
extrude "Panel'" add sketch "Outline (9)" along normal blind 3.175 separate body makes body 23 in component "extra_window"
component "log_1insert_1-5_8" placed x (1, 0, 0) y (0, 1, 0) z (0, 0, 1) at (0, 245, 0)
component "log_1insert_1-1_2_round" placed x (1, 0, 0) y (0, 1, 0) z (0, 0, 1) at (60, 245, 0)
component "log_1insert_1-1_2_octagonal" placed x (1, 0, 0) y (0, 1, 0) z (0, 0, 1) at (120, 245, 0)
component "log_2insert_4-1_2" placed x (1, 0, 0) y (0, 1, 0) z (0, 0, 1) at (0, 175, 0)
component "log_3insert_7-5_8" placed x (1, 0, 0) y (0, 1, 0) z (0, 0, 1) at (0, 35, 0)
component "log_4insert_10-5_8" placed x (1, 0, 0) y (0, 1, 0) z (0, 0, 1) at (0, 0, 0)
component "half_log_4-1_2" placed x (1, 0, 0) y (0, 1, 0) z (0, 0, 1) at (0, 210, 0)
component "half_log_7-1_2" placed x (1, 0, 0) y (0, 1, 0) z (0, 0, 1) at (0, 70, 0)
component "beveled_end_1-1_2" placed x (1, 0, 0) y (0, 1, 0) z (0, 0, 1) at (180, 245, 0)
component "solid_log_1-3_8" placed x (1, 0, 0) y (0, 1, 0) z (0, 0, 1) at (10, 285, 0)
component "solid_log_1-5_8" placed x (1, 0, 0) y (0, 1, 0) z (0, 0, 1) at (50, 285, 0)
component "gable_plastic_8-1_2" placed x (1, 0, 0) y (0, 1, 0) z (0, 0, 1) at (320, 185, 0)
component "gable_plastic_small_2notch" placed x (1, 0, 0) y (0, 1, 0) z (0, 0, 1) at (320, 260, 0)
component "gable_wood_triangle_4x2" placed x (1, 0, 0) y (0, 1, 0) z (0, 0, 1) at (480, 260, 0)
component "shingle_flat_6" placed x (1, 0, 0) y (0, 1, 0) z (0, 0, 1) at (320, 70, 0)
component "shingle_flat_9" placed x (1, 0, 0) y (0, 1, 0) z (0, 0, 1) at (320, 35, 0)
component "shingle_flat_11" placed x (1, 0, 0) y (0, 1, 0) z (0, 0, 1) at (320, 0, 0)
component "shingle_ridge_5-5_8" placed x (1, 0, 0) y (0, 1, 0) z (0, 0, 1) at (480, 150, 0)
component "shingle_ridge_6" placed x (1, 0, 0) y (0, 1, 0) z (0, 0, 1) at (320, 150, 0)
component "shingle_ridge_9" placed x (1, 0, 0) y (0, 1, 0) z (0, 0, 1) at (320, 110, 0)
component "chimney" placed x (1, 0, 0) y (0, 1, 0) z (0, 0, 1) at (100, 290, 0)
component "extra_door" placed x (1, 0, 0) y (0, 1, 0) z (0, 0, 1) at (160, 300, 0)
component "extra_window" placed x (1, 0, 0) y (0, 1, 0) z (0, 0, 1) at (240, 300, 0)
equation "LogDia = 0.75 in" comment "Log diameter"
equation "NotchDepth = 0.1875 in" comment "Notch depth, each side of a log"
equation "NotchCenters = 3 in" comment "Spacing between notch centres"
equation "Clearance = 0.2 mm" comment "Fit clearance per side. Try 0.3 mm for PETG"
equation "PrintFlat = 0.8 mm" comment "Depth of the flat a round log lies on while printing"
equation "MateWidth = LogDia - PrintFlat" comment "Width of a log, half log or gable where it sits in a notch"
equation "NotchWidth = MateWidth + 2 * Clearance" comment "Notch width (mating width plus clearance on each side)"
equation "CourseRise = LogDia - 2 * NotchDepth" comment "Height gained per crossing course"
equation "HalfLogHeight = LogDia - NotchDepth" comment "Half-log height (flat sits at the notch floor)"
equation "GableThk = MateWidth" comment "Gable thickness (fills a notch like a log)"
equation "ShingleThk = 0.125 in" comment "Shingle thickness"
equation "FlatShingleWidth = 0.8 in" comment "Flat shingle width"
equation "RidgeShingleWidth = 1.125 in" comment "Ridge shingle width"
equation "RidgeGrooveWidth = 1.6 mm" comment "Ridge shingle centre groove width"
equation "RidgeGrooveDepth = 0.8 mm" comment "Ridge shingle centre groove depth"
equation "PanelThk = 0.125 in" comment "Door and window panel thickness"
equation "L1a_Length = 1.625 in" comment "Overall length"
equation "L1a_Notches = 1" comment "Number of notch positions"
equation "L1a_FirstNotch = ( L1a_Length - ( L1a_Notches - 1 ) * NotchCenters ) / 2" comment "Centre of the first notch (keeps the row of notches centred)"
equation "L1a_NotchStep = NotchCenters * min(1; L1a_Notches - 1) + 0.001 mm * ( 1 - min(1; L1a_Notches - 1) )" comment "Pattern step: NotchCenters, or about zero when there is only one notch"
equation "d21 = LogDia / 2 - PrintFlat"
equation "d22 = LogDia"
equation "d23 = L1a_Length"
equation "d25 = L1a_FirstNotch - NotchWidth / 2"
equation "d26 = LogDia / 2 - NotchDepth"
equation "d27 = L1a_FirstNotch + NotchWidth / 2"
equation "d28 = LogDia / 2 + 1 mm"
equation "d29 = L1a_FirstNotch - NotchWidth / 2"
equation "d30 = LogDia / 2 - NotchDepth"
equation "d31 = L1a_FirstNotch + NotchWidth / 2"
equation "d32 = LogDia / 2 + 1 mm"
equation "d33 = LogDia"
equation "d35 = max(L1a_Notches; 2)"
equation "d37 = L1a_NotchStep"
equation "L1b_Length = 1.5 in" comment "Overall length"
equation "L1b_Notches = 1" comment "Number of notch positions"
equation "L1b_FirstNotch = ( L1b_Length - ( L1b_Notches - 1 ) * NotchCenters ) / 2" comment "Centre of the first notch (keeps the row of notches centred)"
equation "L1b_NotchStep = NotchCenters * min(1; L1b_Notches - 1) + 0.001 mm * ( 1 - min(1; L1b_Notches - 1) )" comment "Pattern step: NotchCenters, or about zero when there is only one notch"
equation "d43 = LogDia / 2 - PrintFlat"
equation "d44 = LogDia"
equation "d45 = L1b_Length"
equation "d47 = L1b_FirstNotch - NotchWidth / 2"
equation "d48 = LogDia / 2 - NotchDepth"
equation "d49 = L1b_FirstNotch + NotchWidth / 2"
equation "d50 = LogDia / 2 + 1 mm"
equation "d51 = L1b_FirstNotch - NotchWidth / 2"
equation "d52 = LogDia / 2 - NotchDepth"
equation "d53 = L1b_FirstNotch + NotchWidth / 2"
equation "d54 = LogDia / 2 + 1 mm"
equation "d55 = LogDia"
equation "d57 = max(L1b_Notches; 2)"
equation "d59 = L1b_NotchStep"
equation "L1oct_Length = 1.5 in" comment "Overall length"
equation "L1oct_Notches = 1" comment "Number of notch positions"
equation "L1oct_FirstNotch = ( L1oct_Length - ( L1oct_Notches - 1 ) * NotchCenters ) / 2" comment "Centre of the first notch (keeps the row of notches centred)"
equation "L1oct_NotchStep = NotchCenters * min(1; L1oct_Notches - 1) + 0.001 mm * ( 1 - min(1; L1oct_Notches - 1) )" comment "Pattern step: NotchCenters, or about zero when there is only one notch"
equation "d65 = LogDia / 2"
equation "d66 = PrintFlat"
equation "d67 = LogDia / 2"
equation "d68 = LogDia - PrintFlat"
equation "d69 = L1oct_Length"
equation "d71 = LogDia * ( 1 - sqrt(2) / 2 )"
equation "d72 = LogDia / 2 + 1 mm"
equation "d73 = PrintFlat + 1 mm"
equation "d74 = LogDia / 2 + 1 mm"
equation "d75 = L1oct_Length"
equation "d77 = L1oct_FirstNotch - NotchWidth / 2"
equation "d78 = LogDia / 2 - NotchDepth"
equation "d79 = L1oct_FirstNotch + NotchWidth / 2"
equation "d80 = LogDia / 2 + 1 mm"
equation "d81 = L1oct_FirstNotch - NotchWidth / 2"
equation "d82 = LogDia / 2 - NotchDepth"
equation "d83 = L1oct_FirstNotch + NotchWidth / 2"
equation "d84 = LogDia / 2 + 1 mm"
equation "d85 = LogDia"
equation "d87 = max(L1oct_Notches; 2)"